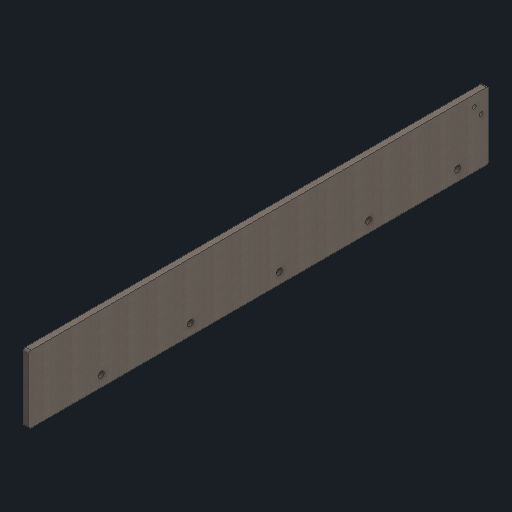
# Autodesk Inventor part: Drag Chain Support (Y Axis)
Saved by Autodesk Inventor 2027.1 (Build 311270010, 270A)
## iProperties
Created: 2026-11-03
Part Number: Drag Chain Support (Y Axis)
Material: Generic
Document SubType Name: Modeling
Designer: Ahmed
Density: 1 g/cm^3
Appearance: Walnut
Author: Ahmed
Autodesk Inventor part; units mm, degrees
ref_plane "YZ Plane" through (0, 0, 0) normal (1, 0, 0) x (0, 1, 0)
ref_plane "XZ Plane" through (0, 0, 0) normal (0, 1, 0) x (-1, 0, 0)
sketch "Sketch1" plane through (0, 0, 0) normal (1, 0, 0) x (0, 1, 0)
  line L0 (2, 0) -> (58.3252, 0)
  line L1 (60.3252, -2) -> (60.3252, -411)
  line L2 (58.3252, -413) -> (2, -413)
  line L3 (0, -411) -> (0, -2)
  arc A0 (60.3252, -2) -> (58.3252, 0) centre (58.3252, -2) ccw
  arc A1 (2, 0) -> (0, -2) centre (2, -2) ccw
  arc A2 (0, -411) -> (2, -413) centre (2, -411) ccw
  arc A3 (58.3252, -413) -> (60.3252, -411) centre (58.3252, -411) ccw
  line L4 (10, 0) -> (10, -450)
  circle A4 centre (10, -65) radius 2.75
  circle A5 centre (10, -145) radius 2.75
  circle A6 centre (10, -225) radius 2.75
  circle A7 centre (10, -305) radius 2.75
  circle A8 centre (10, -385) radius 2.75
  point P0 (0, 0)
  point P1 (60.3252, -413)
  point P2 (60.3252, 0)
  point P3 (0, -413)
  dimension "d0" = 60.3252
  dimension "d1" = 413
  dimension "d2" = 2
  dimension "d5" = 5.5
  dimension "d6" = 65
  dimension "d9" = 80
  dimension "d14" = 10
  constraints: 10 end point, 9 centre point, 9 point on line, 8 point on circle, 8 tangent, 3 equal radius, 2 parallel, 1 horizontal, 1 perpendicular, 1 vertical, 8 other
  measures "d0" distance of point (60.325, -413) point (0, -413)
  measures "d1" distance of point (60.325, 0) point (60.325, -413)
  measures "d2" radius of A0
  measures "d5" diameter of A4
  measures "d6" distance from line of L0 A4.centre
  measures "d9" distance of A4.centre A5.centre
  measures "d14" distance between parallel lines of L3 L4
extrude "Extrusion1" add sketch "Sketch1" along normal blind 5 contours L0 L4 A4 A5 A6 A7 A8 L2 A2 L3 A1 | L0 A0 L1 A3 L2 L4 A8 A7 A6 A5 A4
sketch "Sketch2" plane through (0, 0, 0) normal (-1, 0, 0) x (0, 0, 1)
  line L0 (-404.4996, 40.6552) -> (-404.4996, 43.6552)
  line L1 (-405.9996, 43.6552) -> (-405.9996, 40.6552) construction
  arc A0 (-404.4996, 43.6552) -> (-407.4996, 43.6552) centre (-405.9996, 43.6552) ccw
  line L2 (-407.4996, 43.6552) -> (-407.4996, 40.6552)
  arc A1 (-407.4996, 40.6552) -> (-404.4996, 40.6552) centre (-405.9996, 40.6552) ccw
  circle A2 centre (-405.9996, 42.1552) radius 1.75
  arc A3 (-398.4996, 52.1552) -> (-401.4996, 52.1552) centre (-399.9996, 52.1552) ccw
  arc A4 (-401.4996, 49.1552) -> (-398.4996, 49.1552) centre (-399.9996, 49.1552) ccw
  circle A5 centre (-399.9996, 50.6552) radius 1.75
  line L3 (-401.4996, 52.1552) -> (-401.4996, 49.1552)
  line L4 (-399.9996, 52.1552) -> (-399.9996, 49.1552) construction
  line L5 (-398.4996, 49.1552) -> (-398.4996, 52.1552)
  line L6 (-411, 60.3252) -> (-2, 60.3252) projected
  line L7 (-424.9993, 60.3252) -> (-394.9993, 60.3252)
  line L8 (-394.9993, 60.3252) -> (-394.9993, 31.4852)
  line L9 (-394.9993, 31.4852) -> (-424.9993, 31.4852)
  line L10 (-424.9993, 31.4852) -> (-424.9993, 60.3252)
  line L11 (0, 58.3252) -> (0, 2) projected
  line L12 (-413, 2) -> (-413, 58.3252) projected
  point P0 (0, 0)
  point P1 (-407.4996, 42.1552)
  point P2 (-401.4996, 50.6552)
  dimension "d32" = 3
  dimension "d33" = 3
  dimension "d34" = 3
  dimension "d35" = 3
  dimension "d36" = 3.5
  dimension "d37" = 3.5
  dimension "d38" = 8.5
  dimension "d39" = -6
  dimension "d42" = 30
  dimension "d43" = 28.84
  dimension "d45" = 9.67
  dimension "d46" = 5.0004
  dimension "d51" = 7.0004
  constraints: 24 end point, 8 point on circle, 8 tangent, 6 centre point, 5 parallel, 4 midpoint, 2 coincident, 1 horizontal, 1 perpendicular, 1 point on line, 1 vertical
  measures "d32" diameter of A4
  measures "d33" distance of L4.start L4.end
  measures "d34" diameter of A1
  measures "d35" distance of L1.start L1.end
  measures "d36" diameter of A2
  measures "d37" diameter of A5
  measures "d38" vertical distance of point (-401.5, 50.655) point (-407.5, 42.155)
  measures "d39" horizontal distance of point (-400, 50.655) point (-406, 42.155)
  measures "d42" distance of L8.end L9.end
  measures "d43" distance of L7.end L8.end
  measures "d45" distance from line of L7 point (-400, 50.655)
  measures "d46" distance from line of L8 point (-400, 50.655)
  measures "d51" distance from line of L12 point (-406, 42.155)
extrude "Extrusion2" cut sketch "Sketch2" against normal through all contours A2 L2 L0 | L0 A2 | A2 L2 | L5 A5 L3 | A5 L5 | L3 A5
ref_plane "Work Plane1" through (0, 2, -206.5) normal (0, 0, 1) x (1, 0, 0)
equation "\"d36\" = d40"
equation "\"d37\" = d40"
equation "\"d40\" = d41"
equation "\"GridProcutClearance\" = 5"
equation "\"GridBorderThickness\" = 5"
equation "\"GridBorderFillets\" = 7"
equation "\"GridTotalSize\" = 65"
equation "\"GridRobotClearance\" = 65"
equation "\"AluminiumExtrusionClearance\" = 35"
equation "\"BaseTotalLength\" = 885"
equation "\"WorkspaceLength\" = 515"
equation "\"WorkspaceHeight\" = 183"
equation "\"AxesBaseFillet\" = 15"
equation "\"Zaxis\" = 197"
equation "\"ProductTotalHeight\" = 45"
equation "\"VerticalStroke\" = 105"
equation "\"BackArea\" = 165"
equation "\"CylinderStroke\" = 75"
equation "\"BoxesWidth\" = 125"
equation "\"BaseWoodThickness\" = 7"
equation "\"Kerf\" = 0.3"
equation "\"RxThickness\" = 1.8"
equation "\"support_2\" = 265"
equation "\"d41\" = 3.5"
body "Solid1"
